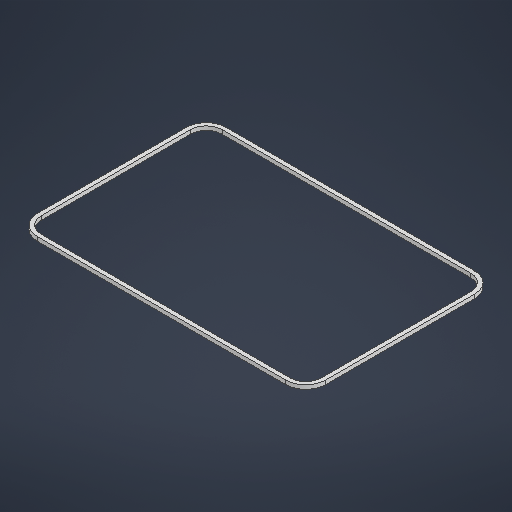
# Autodesk Inventor part: intboite
Saved by Autodesk Inventor 2026.1 (Build 301233020, 233B)
## iProperties
Created: 2026-05-26
Part Number: intboite
Material: Générique
Document SubType Name: Modeling
Designer: matpo
Density: 1 g/cm^3
Appearance: Par défaut
Author: matpo
Autodesk Inventor part; units mm, degrees
ref_plane "YZ Plane" through (0, 0, 0) normal (1, 0, 0) x (0, 1, 0)
ref_plane "XZ Plane" through (0, 0, 0) normal (0, 1, 0) x (-1, 0, 0)
ref_plane "XY Plane" through (0, 0, 0) normal (0, 0, 1) x (1, 0, 0)
sketch "Esquisse1" plane through (0, 0, 0) normal (0, 1, 0) x (-1, 0, 0)
  line L0 (-62.5, -47.5) -> (62.5, -47.5)
  line L1 (72.5, -37.5) -> (72.5, 37.5)
  line L2 (62.5, 47.5) -> (-62.5, 47.5)
  line L3 (-72.5, 37.5) -> (-72.5, -37.5)
  line L4 (-72.5, -47.5) -> (72.5, 47.5) construction
  line L5 (72.5, -47.5) -> (-72.5, 47.5) construction
  arc A0 (72.5, 37.5) -> (62.5, 47.5) centre (62.5, 37.5) ccw
  arc A1 (62.5, -47.5) -> (72.5, -37.5) centre (62.5, -37.5) ccw
  arc A2 (-72.5, -37.5) -> (-62.5, -47.5) centre (-62.5, -37.5) ccw
  arc A3 (-62.5, 47.5) -> (-72.5, 37.5) centre (-62.5, 37.5) ccw
  line L6 (62.5, 45.5) -> (-62.5, 45.5)
  arc A4 (-62.5, 45.5) -> (-70.5, 37.5) centre (-62.5, 37.5) ccw
  line L7 (-70.5, 37.5) -> (-70.5, -37.5)
  arc A5 (-70.5, -37.5) -> (-62.5, -45.5) centre (-62.5, -37.5) ccw
  line L8 (-62.5, -45.5) -> (62.5, -45.5)
  arc A6 (62.5, -45.5) -> (70.5, -37.5) centre (62.5, -37.5) ccw
  line L9 (70.5, -37.5) -> (70.5, 37.5)
  arc A7 (70.5, 37.5) -> (62.5, 45.5) centre (62.5, 37.5) ccw
  point P0 (0, 0)
  dimension "d0" = 145
  dimension "d1" = 95
  dimension "d2" = 10
  dimension "d3" = 2
  constraints: 20 end point, 16 point on circle, 8 centre point, 8 point on line, 8 tangent, 4 parallel, 3 equal radius, 2 midpoint, 2 perpendicular, 1 horizontal, 7 other
  measures "d0" distance of L5.end L4.end
  measures "d1" distance of L5.start L4.end
  measures "d2" radius of A0
  measures "d3" radial gap between concentric circles of A0 A7
extrude "Extrusion1" add sketch "Esquisse1" along normal blind 2
